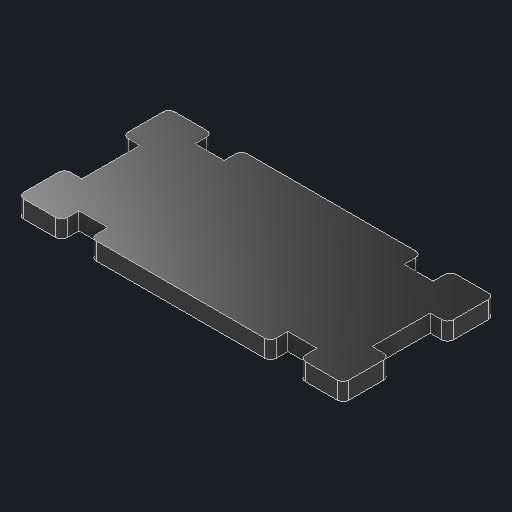
# Autodesk Inventor part: RxCeil
Saved by Autodesk Inventor 2027.1 (Build 311270010, 270A)
## iProperties
Created: 2026-10-19
Part Number: RxCeil
Material: MDF Medium Density Fiberboard
Document SubType Name: Modeling
Designer: SDS Scholar
Density: 0.8 g/cm^3
Appearance: Glossy - Black
Mass: 3.19816 g
Surface Area: 32.4453 cm^2
Volume: 3.9977 cm^3
Author: SDS Scholar
Autodesk Inventor part; units mm, degrees
ref_plane "YZ Plane" through (0, 0, 0) normal (1, 0, 0) x (0, 1, 0)
ref_plane "XZ Plane" through (0, 0, 0) normal (0, 1, 0) x (-1, 0, 0)
ref_plane "XY Plane" through (0, 0, 0) normal (0, 0, 1) x (1, 0, 0)
sketch "Sketch1" plane through (0, 0, 0) normal (0, 1, 0) x (-1, 0, 0)
  line L0 (28, 13) -> (-28, 13)
  line L1 (-28, 13) -> (-28, -13)
  line L2 (-28, -13) -> (28, -13)
  line L3 (28, -13) -> (28, 13)
  line L4 (-28, 5) -> (-25, 5)
  line L5 (-25, 5) -> (-25, -5)
  line L6 (-25, -5) -> (-28, -5)
  line L7 (-28, -5) -> (-28, 5)
  line L8 (0, 13) -> (0, -13) construction
  line L9 (-20.5, 13) -> (-15.5, 13)
  line L10 (-15.5, 13) -> (-15.5, 10)
  line L11 (-15.5, 10) -> (-20.5, 10)
  line L12 (-20.5, 10) -> (-20.5, 13)
  line L13 (-15.5, -13) -> (-20.5, -13)
  line L14 (-20.5, -13) -> (-20.5, -10)
  line L15 (-20.5, -10) -> (-15.5, -10)
  line L16 (-15.5, -10) -> (-15.5, -13)
  line L17 (28, 5) -> (25, 5)
  line L18 (25, 5) -> (25, -5)
  line L19 (25, -5) -> (28, -5)
  line L20 (15.5, 13) -> (15.5, 10)
  line L21 (15.5, 10) -> (20.5, 10)
  line L22 (20.5, 10) -> (20.5, 13)
  line L23 (20.5, -13) -> (20.5, -10)
  line L24 (20.5, -10) -> (15.5, -10)
  line L25 (15.5, -10) -> (15.5, -13)
  point P0 (0, 0)
  point P1 (28, 0)
  point P2 (-25, 0)
  point P3 (-28, 0)
  point P4 (-18, 10)
  point P5 (-18, -10)
  point P6 (-20.5, -13)
  point P7 (15.5, -13)
  point P8 (20.5, -13)
  point P9 (20.5, 13)
  point P10 (15.5, 13)
  point P11 (-15.5, 13)
  dimension "d0" = 56
  dimension "d1" = 26
  dimension "d2" = 10
  dimension "d3" = 3
  dimension "d4" = 5
  dimension "d5" = 3
  dimension "d6" = 10
  dimension "d7" = 5
  dimension "d8" = 3
  dimension "d9" = 10
  constraints: 52 end point, 12 symmetric about line, 8 parallel, 7 midpoint, 4 horizontal, 4 perpendicular, 3 point on line, 2 horizontal alignment, 1 vertical, 1 vertical alignment
  measures "d0" distance of L0.start L0.end
  measures "d1" distance of L0.end L1.end
  measures "d2" distance of L4.end L5.end
  measures "d3" distance of L4.start L4.end
  measures "d4" distance of L10.end L11.end
  measures "d5" distance of L11.end L9.start
  measures "d6" distance from line of L1 point (-18, 10)
  measures "d7" distance of L14.end L15.end
  measures "d8" distance of L13.end L14.end
  measures "d9" distance from line of L1 point (-18, -10)
extrude "Extrusion1" add sketch "Sketch1" along normal blind 3 contours L3 L17 L18 L19 L2 L23 L24 L25 L16 L15 L14 L1 L6 L5 L4 L0 L12 L11 L10 L20 L21 L22
fillet "Fillet1" radius 1 16 edges at (28, 1.5, 13) (28, 1.5, -13) (-28, 1.5, 13) (-28, 1.5, -13) (-20.5, 1.5, -13) (-15.5, 1.5, -13) (15.5, 1.5, -13) (20.5, 1.5, -13) (-28, 1.5, 5) (-20.5, 1.5, 13) (-15.5, 1.5, 13) (15.5, 1.5, 13) (20.5, 1.5, 13) (28, 1.5, 5) (28, 1.5, -5) (-28, 1.5, -5)
equation "\"GridProcutClearance\" = 5"
equation "\"GridBorderThickness\" = 5"
equation "\"GridBorderFillets\" = 7"
equation "\"GridTotalSize\" = 65"
equation "\"GridRobotClearance\" = 65"
equation "\"AluminiumExtrusionClearance\" = 35"
equation "\"BaseTotalLength\" = 885"
equation "\"WorkspaceLength\" = 515"
equation "\"WorkspaceHeight\" = 183"
equation "\"AxesBaseFillet\" = 15"
equation "\"Zaxis\" = 197"
equation "\"ProductTotalHeight\" = 45"
equation "\"VerticalStroke\" = 105"
equation "\"BackArea\" = 165"
equation "\"CylinderStroke\" = 75"
equation "\"BoxesWidth\" = 125"
equation "\"BaseWoodThickness\" = 7"
equation "\"Kerf\" = 0.3"
equation "\"RxThickness\" = 1.8"
equation "\"support_2\" = 265"
body "Solid1"
